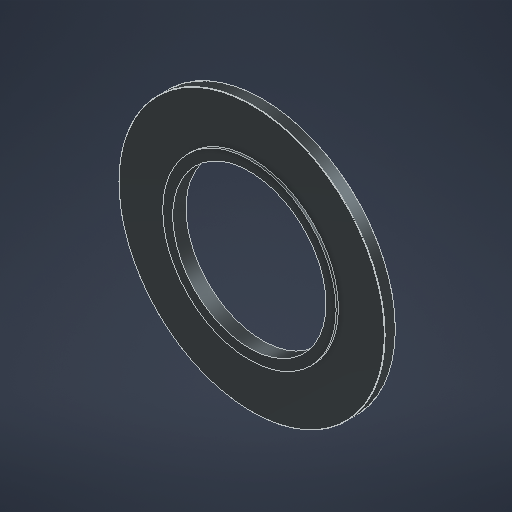
# Autodesk Inventor part: disk 1
Saved by Autodesk Inventor 2027 (Build 310192060, 192F)
## iProperties
Created: 2026-06-30
Part Number: disk 1
Material: Iron, Cast
Document SubType Name: Modeling
Designer: ElieH
Density: 7.15 g/cm^3
Appearance: Iron Gray
Author: ElieH
Autodesk Inventor part; units mm, degrees
ref_plane "YZ Plane" through (0, 0, 0) normal (1, 0, 0) x (0, 1, 0)
ref_plane "XZ Plane" through (0, 0, 0) normal (0, 1, 0) x (-1, 0, 0)
ref_plane "XY Plane" through (0, 0, 0) normal (0, 0, 1) x (1, 0, 0)
sketch "Sketch1" plane through (0, 0, 0) normal (0, 0, 1) x (1, 0, 0)
  circle A0 centre (0, 0) radius 145.2753
  circle A1 centre (0, 0) radius 94.6404
  circle A2 centre (0, 0) radius 94.6404
  circle A3 centre (0, 0) radius 83.6422
  dimension "d0" = 290.5506
  dimension "d1" = 189.2808
  dimension "d2" = 189.2808
  dimension "d3" = 167.2844
  constraints: 4 centre point, 4 coincident
  measures "d0" diameter of A0
  measures "d1" diameter of A1
  measures "d2" diameter of A2
  measures "d3" diameter of A3
extrude "Extrusion1" add sketch "Sketch1" along normal blind 11.875 contours A0
fillet "Fillet1" radius 0.375 1 edges at (-145.2753, 0, 11.875)
fillet "Fillet2" radius 0.375 1 edges at (-145.2753, 0, 0)
extrude "Extrusion2" add sketch "Sketch1" along normal blind 14.375 contours A1
